Autodesk Fusion 360 part; units mm, degrees
(part 2 of 2)
  line L968 (-16.9, 13.5) -> (-16.9088, 13.3328)
  line L969 (-16.9088, 13.3328) -> (-16.935, 13.1673)
  line L970 (-16.935, 13.1673) -> (-16.9783, 13.0056)
  line L971 (-16.9783, 13.0056) -> (-17.0383, 12.8492)
  line L972 (-17.0383, 12.8492) -> (-17.1144, 12.7)
  line L973 (-17.1144, 12.7) -> (-17.2056, 12.5595)
  line L974 (-17.2056, 12.5595) -> (-17.311, 12.4294)
  line L975 (-17.311, 12.4294) -> (-17.4294, 12.311)
  line L976 (-17.4294, 12.311) -> (-17.5595, 12.2056)
  line L977 (-17.5595, 12.2056) -> (-17.7, 12.1144)
  line L978 (-17.7, 12.1144) -> (-17.8492, 12.0383)
  line L979 (-17.8492, 12.0383) -> (-18.0056, 11.9783)
  line L980 (-18.0056, 11.9783) -> (-18.1673, 11.935)
  line L981 (-18.1673, 11.935) -> (-18.3328, 11.9088)
  line L982 (-18.3328, 11.9088) -> (-18.5, 11.9)
  line L983 (-18.5, 11.9) -> (-18.6672, 11.9088)
  line L984 (18.3328, 11.9088) -> (18.1673, 11.935)
  line L985 (18.1673, 11.935) -> (18.0056, 11.9783)
  line L986 (18.0056, 11.9783) -> (17.8492, 12.0383)
  line L987 (17.8492, 12.0383) -> (17.7, 12.1144)
  line L988 (17.7, 12.1144) -> (17.5595, 12.2056)
  line L989 (17.5595, 12.2056) -> (17.4294, 12.311)
  line L990 (17.4294, 12.311) -> (17.311, 12.4294)
  line L991 (17.311, 12.4294) -> (17.2056, 12.5595)
  line L992 (17.2056, 12.5595) -> (17.1144, 12.7)
  line L993 (17.1144, 12.7) -> (17.0383, 12.8492)
  line L994 (17.0383, 12.8492) -> (16.9783, 13.0056)
  line L995 (16.9783, 13.0056) -> (16.935, 13.1673)
  line L996 (16.935, 13.1673) -> (16.9088, 13.3328)
  line L997 (16.9088, 13.3328) -> (16.9, 13.5)
  line L998 (16.9, 13.5) -> (16.9088, 13.6672)
  line L999 (16.9088, 13.6672) -> (16.935, 13.8327)
  line L1000 (16.935, 13.8327) -> (16.9783, 13.9944)
  line L1001 (16.9783, 13.9944) -> (17.0383, 14.1508)
  line L1002 (17.0383, 14.1508) -> (17.1144, 14.3)
  line L1003 (17.1144, 14.3) -> (17.2056, 14.4405)
  line L1004 (17.2056, 14.4405) -> (17.311, 14.5706)
  line L1005 (17.311, 14.5706) -> (17.4294, 14.689)
  line L1006 (17.4294, 14.689) -> (17.5595, 14.7944)
  line L1007 (17.5595, 14.7944) -> (17.7, 14.8856)
  line L1008 (17.7, 14.8856) -> (17.8492, 14.9617)
  line L1009 (17.8492, 14.9617) -> (18.0056, 15.0217)
  line L1010 (18.0056, 15.0217) -> (18.1673, 15.065)
  line L1011 (18.1673, 15.065) -> (18.3328, 15.0912)
  line L1012 (18.3328, 15.0912) -> (18.5, 15.1)
  line L1013 (18.5, 15.1) -> (18.6672, 15.0912)
  line L1014 (18.6672, 15.0912) -> (18.8327, 15.065)
  line L1015 (18.8327, 15.065) -> (18.9944, 15.0217)
  line L1016 (18.9944, 15.0217) -> (19.1508, 14.9617)
  line L1017 (19.1508, 14.9617) -> (19.3, 14.8856)
  line L1018 (19.3, 14.8856) -> (19.4405, 14.7944)
  line L1019 (19.4405, 14.7944) -> (19.5706, 14.689)
  line L1020 (19.5706, 14.689) -> (19.689, 14.5706)
  line L1021 (19.689, 14.5706) -> (19.7944, 14.4405)
  line L1022 (19.7944, 14.4405) -> (19.8856, 14.3)
  line L1023 (19.8856, 14.3) -> (19.9617, 14.1508)
  line L1024 (19.9617, 14.1508) -> (20.0217, 13.9944)
  line L1025 (20.0217, 13.9944) -> (20.065, 13.8327)
  line L1026 (20.065, 13.8327) -> (20.0912, 13.6672)
  line L1027 (20.0912, 13.6672) -> (20.1, 13.5)
  line L1028 (20.1, 13.5) -> (20.0912, 13.3328)
  line L1029 (20.0912, 13.3328) -> (20.065, 13.1673)
  line L1030 (20.065, 13.1673) -> (20.0217, 13.0056)
  line L1031 (20.0217, 13.0056) -> (19.9617, 12.8492)
  line L1032 (19.9617, 12.8492) -> (19.8856, 12.7)
  line L1033 (19.8856, 12.7) -> (19.7944, 12.5595)
  line L1034 (19.7944, 12.5595) -> (19.689, 12.4294)
  line L1035 (19.689, 12.4294) -> (19.5706, 12.311)
  line L1036 (19.5706, 12.311) -> (19.4405, 12.2056)
  line L1037 (19.4405, 12.2056) -> (19.3, 12.1144)
  line L1038 (19.3, 12.1144) -> (19.1508, 12.0383)
  line L1039 (19.1508, 12.0383) -> (18.9944, 11.9783)
  line L1040 (18.9944, 11.9783) -> (18.8327, 11.935)
  line L1041 (18.8327, 11.935) -> (18.6672, 11.9088)
  line L1042 (18.6672, 11.9088) -> (18.5, 11.9)
  line L1043 (18.5, 11.9) -> (18.3328, 11.9088)
extrude "Extrude1" add sketch "Sketch1" along normal blind 3

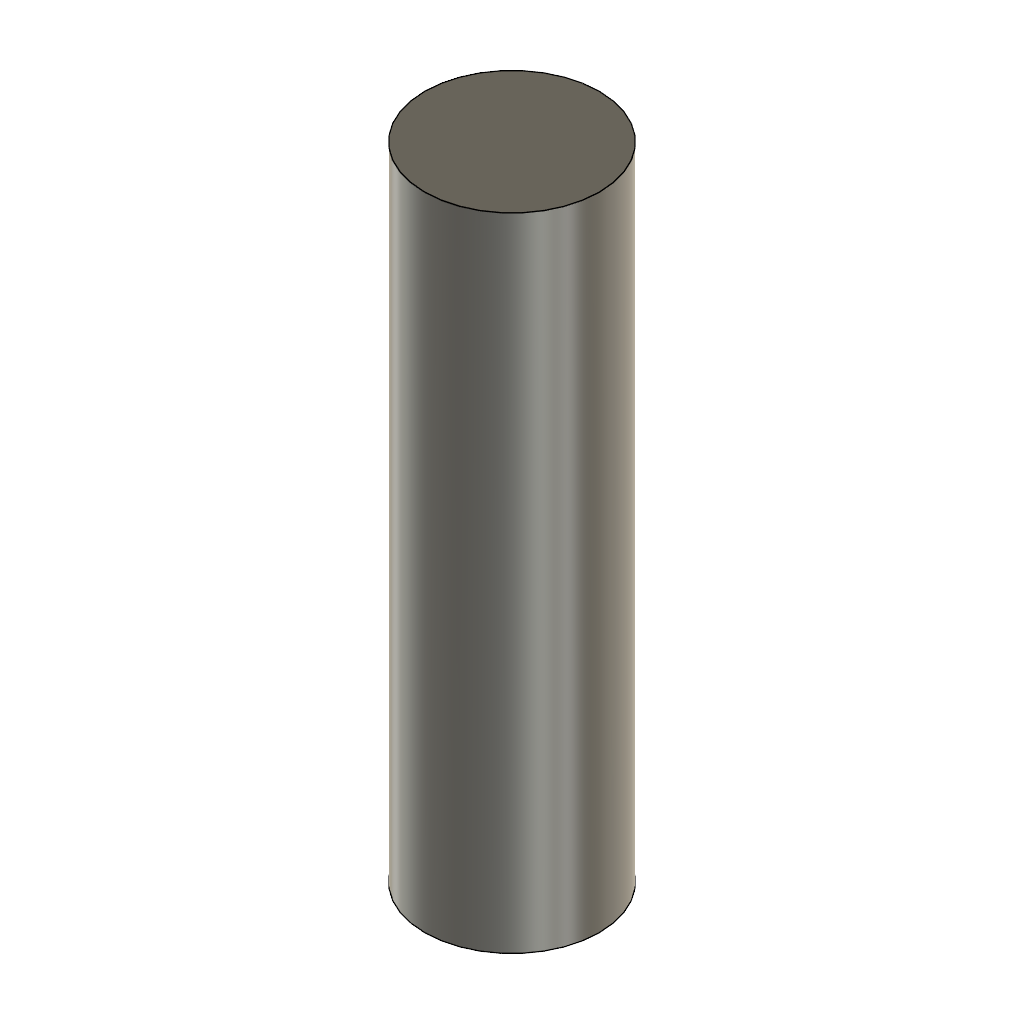
design "External1"
part number: 2026-11-21-16-18-45-720
Autodesk Fusion 360 part; units mm, degrees
derive "DerivedContext1"
sketch "sketch 553" plane through (0, 0, 0) normal (0, 0, 1) x (1, 0, 0)
  circle A0 centre (58.3713, 210.7701) radius 1.8385
extrude "Extrude1" add sketch "sketch 553" against normal blind 13.5
